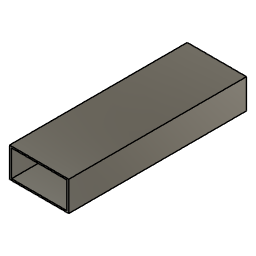
180degreesangle (Autodesk Fusion 360 design; units mm, degrees)
Autodesk Fusion 360 part; units mm, degrees
sketch "Sketch1" plane through (0, 0, 0) normal (0, 0, 1) x (1, 0, 0)
  line L0 (0, 0) -> (30, 0)
  line L1 (30, 0) -> (30, 90)
  line L2 (30, 90) -> (0, 90)
  line L3 (0, 90) -> (0, 0)
  dimension "d1" = 30
  dimension "d2" = 90
  constraint horizontal L0
  constraint vertical L1
  constraint horizontal L2
  constraint vertical L3
  constraint coincident L0.start L3.end
  measures "d1" distance of L0.start L0.end
  measures "d2" distance of L0.start L2.end
extrude "Extrude1" add sketch "Sketch1" along normal blind 15
sketch "Sketch2" plane through (0, 0, 0) normal (0, -1, 0) x (1, 0, 0)
  line L0 (0, 0) -> (30, 0)
  line L1 (30, 0) -> (30, 15)
  line L2 (30, 15) -> (0, 15)
  line L3 (0, 15) -> (0, 0)
  line L4 (1, 14.25) -> (29, 14.25)
  line L5 (29, 14.25) -> (29, 0.75)
  line L6 (29, 0.75) -> (1, 0.75)
  line L7 (1, 0.75) -> (1, 14.25)
  line L8 (1, 14.25) -> (1, 15)
  line L9 (1, 14.25) -> (0, 14.25)
  line L10 (1, 0.75) -> (1, 0)
  line L11 (29, 14.25) -> (30, 14.25)
  dimension "d5" = 13.5
  constraint horizontal L4
  constraint vertical L5
  constraint horizontal L6
  constraint vertical L7
  constraint coincident L2 L8.end
  constraint perpendicular L2 L8
  constraint coincident L3 L9.end
  constraint perpendicular L3 L9
  constraint coincident L0 L10.end
  constraint perpendicular L0 L10
  constraint coincident L1 L11.end
  constraint perpendicular L1 L11
  constraint equal L9 L11
  constraint equal L8 L10
  measures "d5" distance of L4.start L6.end
extrude "Extrude2" cut sketch "Sketch2" against normal blind 30 contours L4 L5 L6 L7
sketch "Sketch3" plane through (0, 90, 0) normal (0, 1, 0) x (-1, 0, 0)
  line L0 (-30, 0) -> (0, 0)
  line L1 (0, 0) -> (0, 15)
  line L2 (0, 15) -> (-30, 15)
  line L3 (-30, 15) -> (-30, 0)
  line L4 (-29, 14.25) -> (-1, 14.25)
  line L5 (-1, 14.25) -> (-1, 0.75)
  line L6 (-1, 0.75) -> (-29, 0.75)
  line L7 (-29, 0.75) -> (-29, 14.25)
  line L8 (-29, 14.25) -> (-29, 15)
  line L9 (-29, 14.25) -> (-30, 14.25)
  line L10 (-29, 0.75) -> (-29, 0)
  line L11 (-1, 14.25) -> (0, 14.25)
  dimension "d8" = 13.5
  constraint horizontal L4
  constraint vertical L5
  constraint horizontal L6
  constraint vertical L7
  constraint coincident L2 L8.end
  constraint perpendicular L2 L8
  constraint coincident L3 L9.end
  constraint perpendicular L3 L9
  constraint coincident L0 L10.end
  constraint perpendicular L0 L10
  constraint coincident L1 L11.end
  constraint perpendicular L1 L11
  constraint equal L9 L11
  constraint equal L8 L10
  measures "d8" distance of L4.start L6.end
extrude "Extrude3" cut sketch "Sketch3" against normal blind 30 contours L4 L5 L6 L7
sketch "Sketch4" plane through (0, 0, 0) normal (0, 0, -1) x (1, 0, 0)
  line L0 (0, 0) -> (0, -90)
  line L1 (0, -90) -> (30, -90)
  line L2 (30, -90) -> (30, 0)
  line L3 (30, 0) -> (0, 0)
  line L4 (1, -31) -> (29, -31)
  line L5 (29, -31) -> (29, -59)
  line L6 (29, -59) -> (1, -59)
  line L7 (1, -59) -> (1, -31)
  line L8 (1, -31) -> (0, -31)
  line L9 (1, -31) -> (1, 0)
  line L10 (29, -31) -> (30, -31)
  line L11 (1, -59) -> (1, -90)
  dimension "d11" = 28
  dimension "d12" = 28
  constraint horizontal L4
  constraint vertical L5
  constraint horizontal L6
  constraint vertical L7
  constraint coincident L0 L8.end
  constraint perpendicular L0 L8
  constraint coincident L3 L9.end
  constraint perpendicular L3 L9
  constraint coincident L2 L10.end
  constraint perpendicular L2 L10
  constraint coincident L1 L11.end
  constraint perpendicular L1 L11
  constraint equal L8 L10
  constraint equal L9 L11
  measures "d11" distance of L4.start L4.end
  measures "d12" distance of L4.start L6.end
extrude "Extrude4" cut sketch "Sketch4" against normal blind 14 contours L4 L5 L6 L7
sketch "Sketch5" plane through (0, 30, 0) normal (0, -1, 0) x (1, 0, 0)
  line L0 (1, 0.75) -> (29, 0.75)
  line L1 (29, 0.75) -> (29, 14.25)
  line L2 (29, 14.25) -> (1, 14.25)
  line L3 (1, 14.25) -> (1, 0.75)
  line L4 (1, 0.75) -> (29, 0.75)
  line L5 (29, 0.75) -> (29, 10.75)
  line L6 (29, 10.75) -> (1, 10.75)
  line L7 (1, 10.75) -> (1, 0.75)
  dimension "d15" = 10
  constraint horizontal L4
  constraint vertical L5
  constraint horizontal L6
  constraint vertical L7
  constraint coincident L0.start L3.end
  measures "d15" distance of L0.start L6.end
extrude "Extrude5" cut sketch "Sketch5" against normal blind 50 contours L0 L1 L3 L4 L5 L6 L7
